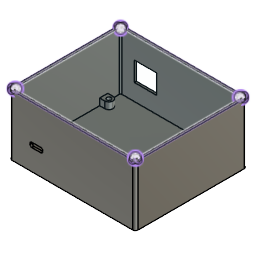
ebr-case (Autodesk Fusion 360 design; units mm, degrees)
Autodesk Fusion 360 part; units mm, degrees
sketch "Skizze1" plane through (0, 0, 0) normal (0, 0, 1) x (1, 0, 0)
  line L0 (0, 0) -> (90, 0) construction
  line L1 (90, 0) -> (90, 70) construction
  line L2 (90, 70) -> (0, 70) construction
  line L3 (0, 70) -> (0, 0) construction
  circle A0 centre (3.5, 67) radius 1.6
  circle A1 centre (86.5, 67) radius 1.6
  circle A2 centre (86.5, 3) radius 1.6
  circle A3 centre (3.5, 3) radius 1.6
  circle A4 centre (3.5, 67) radius 3
  circle A5 centre (86.5, 67) radius 3
  circle A6 centre (86.5, 3) radius 3
  circle A7 centre (3.5, 3) radius 3
  line L4 (-0.4, 79.6) -> (90.4, 79.6)
  line L5 (90.4, 79.6) -> (90.4, -0.2)
  line L6 (90.4, -0.2) -> (-0.4, -0.2)
  line L7 (-0.4, -0.2) -> (-0.4, 79.6)
  line L8 (92, -1.8) -> (-2, -1.8)
  line L9 (-2, -1.8) -> (-2, 81.2)
  line L10 (-2, 81.2) -> (92, 81.2)
  line L11 (92, 81.2) -> (92, -1.8)
  line L12 (3.5, 64) -> (-0.4, 64)
  line L13 (3.5, 70) -> (-0.4, 70)
  line L14 (6.5, 3) -> (6.5, -0.2)
  line L15 (3.5, 6) -> (-0.4, 6)
  line L16 (83.5, 3) -> (83.5, -0.2)
  line L17 (86.5, 6) -> (90.4, 6)
  line L18 (86.5, 64) -> (90.4, 64)
  line L19 (86.5, 70) -> (90.4, 70)
  point P0 (3.5, 67)
  point P1 (86.5, 67)
  point P2 (3.5, 3)
  point P3 (86.5, 3)
  dimension "d1" = 90
  dimension "d2" = 70
  dimension "d3" = 3.5
  dimension "d4" = 3
  dimension "d5" = 3.5
  dimension "d6" = 3
  dimension "d7" = 3.2
  dimension "d8" = 3.2
  dimension "d9" = 3.2
  dimension "d10" = 3.2
  dimension "d11" = 9.6
  dimension "d12" = 0.4
  dimension "d13" = 0.4
  dimension "d14" = 0.2
  dimension "d15" = -1.6
  constraint horizontal L0
  constraint vertical L1
  constraint horizontal L2
  constraint vertical L3
  constraint coincident L0.start L3.end
  constraint coincident P0 A0.centre
  constraint coincident P1 A1.centre
  constraint coincident P3 A2.centre
  constraint coincident P2 A3.centre
  constraint tangent L2 A4
  constraint tangent L2 A5
  constraint tangent L0 A6
  constraint tangent L0 A7
  constraint horizontal L4
  constraint vertical L5
  constraint horizontal L6
  constraint vertical L7
  constraint coincident A4 L12.start
  constraint coincident L7 L12.end
  constraint tangent A4 L12
  constraint perpendicular L7 L12
  constraint coincident A4 L13.start
  constraint coincident L7 L13.end
  constraint tangent A4 L13
  constraint perpendicular L7 L13
  constraint coincident A7 L14.start
  constraint coincident L6 L14.end
  constraint tangent A7 L14
  constraint perpendicular L6 L14
  constraint coincident A7 L15.start
  constraint coincident L7 L15.end
  constraint tangent A7 L15
  constraint perpendicular L7 L15
  constraint coincident A6 L16.start
  constraint coincident L6 L16.end
  constraint tangent A6 L16
  constraint perpendicular L6 L16
  constraint coincident A6 L17.start
  constraint coincident L5 L17.end
  constraint tangent A6 L17
  constraint perpendicular L5 L17
  constraint coincident A5 L18.start
  constraint coincident L5 L18.end
  constraint tangent A5 L18
  constraint perpendicular L5 L18
  constraint coincident A5 L19.start
  constraint coincident L5 L19.end
  constraint tangent A5 L19
  constraint perpendicular L5 L19
  measures "d1" distance of L0.start L0.end
  measures "d2" distance of L0.start L2.end
  measures "d3" distance of L3 P0
  measures "d4" distance of L2 P0
  measures "d5" distance of L1 P1
  measures "d6" distance of L0 P2
  measures "d7" diameter of A0
  measures "d8" diameter of A1
  measures "d9" diameter of A2
  measures "d10" diameter of A3
  measures "d11" distance of L2 L4
  measures "d12" distance of L3 L7
  measures "d13" distance of L1 L5
  measures "d14" distance of L0 L6
extrude "Extrusion1" add sketch "Skizze1" along normal blind 2 contours A4 A5 A6 A7 L4 L5 L6 L7 L12 L13 L14 L15 L16 L17 L18 L19 makes body 1
extrude "Extrusion2" add sketch "Skizze1" along normal blind 4 separate body contours A0 | A1 | A2 | A3 makes body 2 at (2.3828, 65.8546, 2.6667) makes body 3 at (86.5399, 68.5995, 2.6667) makes body 4 at (5.098, 2.9202, 2.6667) makes body 5 at (86.5399, 4.5995, 2.6667)
extrude "Extrusion3" add sketch "Skizze1" along normal blind 7 contours A4 | A4 L7 L12 L13 | A7 L6 L7 L14 L15 | A7 | A5 L5 L18 L19 | A5 | A6 L5 L6 L16 L17 | A6 bodies 1 2 3 4 5
extrude "Extrusion4" add sketch "Skizze1" along normal blind 45 contours L8 L9 L10 L11 bodies 1
sketch "Skizze2" plane through (0, 81.2, 0) normal (0, -1, 0) x (1, 0, 0)
  line L0 (-1.8, 0) -> (91.8, 0)
  line L1 (91.8, 0) -> (91.8, 45)
  line L2 (91.8, 45) -> (-1.8, 45)
  line L3 (-1.8, 45) -> (-1.8, 0)
  line L4 (-1.8, 8.3) -> (91.8, 8.3) construction
  line L5 (91.8, 0) -> (-1.8, 0)
  line L6 (9.8, 28.7) -> (26.3, 28.7)
  line L7 (26.3, 28.7) -> (26.3, 14.3)
  line L8 (26.3, 14.3) -> (9.8, 14.3)
  line L9 (9.8, 14.3) -> (9.8, 28.7)
  line L10 (-0.2, 2) -> (90.2, 2)
  line L11 (90.2, 2) -> (90.2, 45)
  line L12 (90.2, 45) -> (-0.2, 45)
  line L13 (-0.2, 45) -> (-0.2, 2)
  line L14 (92, 0) -> (-2, 0)
  line L15 (-2, 0) -> (-2, 45)
  line L16 (-2, 45) -> (92, 45)
  line L17 (92, 45) -> (92, 0)
  point P0 (90.2, 0)
  dimension "d24" = 8.3
  dimension "d25" = 16.5
  dimension "d26" = 14.4
  dimension "d27" = 6
  dimension "d38" = 9.8
  constraint coincident L3 L4.start
  constraint coincident L1 L4.end
  constraint perpendicular L1 L4
  constraint horizontal L6
  constraint vertical L7
  constraint horizontal L8
  constraint vertical L9
  measures "d24" distance of L4 L5
  measures "d25" distance of L6.start L6.end
  measures "d26" distance of L6.start L8.end
  measures "d27" distance of L4 L8
  measures "d38" distance of L9 origin
extrude "Extrusion5" cut sketch "Skizze2" along normal blind 2 contours L6 L7 L8 L9 bodies 1
sketch "Skizze3" plane through (0, -1.8, 0) normal (0, 1, 0) x (-1, 0, 0)
  line L0 (-91.8, 0) -> (1.8, 0)
  line L1 (1.8, 0) -> (1.8, 45)
  line L2 (1.8, 45) -> (-91.8, 45)
  line L3 (-91.8, 45) -> (-91.8, 0)
  line L4 (1.8, 8.3) -> (-91.8, 8.3)
  line L5 (-21.8, 19.05) -> (-14.8, 19.05)
  line L6 (-13.6, 17.85) -> (-13.6, 16.85)
  line L7 (-14.8, 15.65) -> (-21.8, 15.65)
  line L8 (-23, 16.85) -> (-23, 17.85)
  arc A0 (-21.8, 19.05) -> (-23, 17.85) centre (-21.8, 17.85) ccw
  arc A1 (-23, 16.85) -> (-21.8, 15.65) centre (-21.8, 16.85) ccw
  arc A2 (-14.8, 15.65) -> (-13.6, 16.85) centre (-14.8, 16.85) ccw
  arc A3 (-13.6, 17.85) -> (-14.8, 19.05) centre (-14.8, 17.85) ccw
  line L9 (2, 0) -> (-92, 0)
  line L10 (-92, 0) -> (-92, 45)
  line L11 (-92, 45) -> (2, 45)
  line L12 (2, 45) -> (2, 0)
  point P0 (-23, 19.05)
  point P1 (-13.6, 19.05)
  point P2 (-23, 15.65)
  dimension "d31" = 9.4
  dimension "d32" = 3.4
  dimension "d33" = 7.35
  dimension "d35" = 1.2
  dimension "d39" = 13.6
  constraint horizontal L5
  constraint vertical L6
  constraint horizontal L7
  constraint vertical L8
  constraint coincident P0 L5
  constraint coincident P0 L8
  constraint tangent L5 A0
  constraint tangent L8 A0
  constraint coincident P2 L7
  constraint coincident P2 L8
  constraint tangent L7 A1
  constraint tangent L8 A1
  constraint equal A0 A1
  constraint tangent L6 A2
  constraint tangent L7 A2
  constraint equal A0 A2
  constraint coincident P1 L5
  constraint coincident P1 L6
  constraint tangent L5 A3
  constraint tangent L6 A3
  constraint equal A0 A3
  measures "d31" distance of P0 P1
  measures "d32" distance of P0 P2
  measures "d33" distance of L4 L7
  measures "d35" radius of A0
  measures "d39" horizontal distance of P1 origin
extrude "Extrusion6" cut sketch "Skizze3" along normal blind 2 contours L5 L6 L7 L8 A0 A1 A2 A3 bodies 1
fillet "Abrundung1" radius 1 4 edges at (90.4, 79.6, 23.5) (90.4, -0.2, 26) (-0.4, -0.2, 26) (-0.4, 79.6, 23.5) on bodies 1
fillet "Abrundung2" radius 2 4 edges at (-2, -1.8, 22.5) (92, -1.8, 22.5) (92, 81.2, 22.5) (-2, 81.2, 22.5) on bodies 1
sketch "Skizze4" plane through (0, 0, 45) normal (0, 0, 1) x (-1, 0, 0)
  arc A0 (0, -81.2) -> (2, -79.2) centre (0, -79.2) ccw
  line L0 (2, -79.2) -> (2, -0.2)
  arc A1 (2, -0.2) -> (0, 1.8) centre (0, -0.2) ccw
  line L1 (0, 1.8) -> (-90, 1.8)
  arc A2 (-90, 1.8) -> (-92, -0.2) centre (-90, -0.2) ccw
  line L2 (-92, -0.2) -> (-92, -79.2)
  arc A3 (-92, -79.2) -> (-90, -81.2) centre (-90, -79.2) ccw
  line L3 (-90, -81.2) -> (0, -81.2)
  line L4 (-89.4, 0.2) -> (-0.6, 0.2) construction
  arc A4 (0.4, -0.8) -> (-0.6, 0.2) centre (-0.6, -0.8) ccw construction
  line L5 (0.4, -0.8) -> (0.4, -78.6) construction
  arc A5 (-0.6, -79.6) -> (0.4, -78.6) centre (-0.6, -78.6) ccw construction
  line L6 (-0.6, -79.6) -> (-89.4, -79.6) construction
  arc A6 (-90.4, -78.6) -> (-89.4, -79.6) centre (-89.4, -78.6) ccw construction
  line L7 (-90.4, -78.6) -> (-90.4, -0.8) construction
  arc A7 (-89.4, 0.2) -> (-90.4, -0.8) centre (-89.4, -0.8) ccw construction
  arc A8 (0.16, -0.8) -> (-0.6, -0.04) centre (-0.6, -0.8) ccw
  line L8 (-89.4, -0.04) -> (-0.6, -0.04)
  arc A9 (-89.4, -0.04) -> (-90.16, -0.8) centre (-89.4, -0.8) ccw
  line L9 (-90.16, -78.6) -> (-90.16, -0.8)
  arc A10 (-90.16, -78.6) -> (-89.4, -79.36) centre (-89.4, -78.6) ccw
  line L10 (-0.6, -79.36) -> (-89.4, -79.36)
  arc A11 (-0.6, -79.36) -> (0.16, -78.6) centre (-0.6, -78.6) ccw
  line L11 (0.16, -0.8) -> (0.16, -78.6)
  dimension "d44" = 0.24
equation "d5 = d3"
equation "d8 = d7"
equation "d9 = d7"
equation "d10 = d7"
